Autodesk Fusion 360 part; units mm, degrees
(part 2 of 4)
revolve "Nest around the floor radius'" cut sketch "Sketch4 (3)" angle 90 about axis through (-24.07, -24.07, 3.45) along (0, 0, -1) bodies 4 in component "PRT-CORNER"
sketch "Sketch5 (2)" plane through (0, 0, 0) normal (0, 0, 1) x (1, 0, 0) in component "PRT-CORNER"
  line L0 (-23.8, -55) -> (-16.2, -55)
  line L1 (-16.2, -55) -> (-16.2, -40)
  line L2 (-16.2, -40) -> (-23.8, -40)
  line L3 (-23.8, -40) -> (-23.8, -55)
  dimension "d448" = 55
  dimension "d449" = 16.2
  dimension "d450" = 40
  dimension "d451" = 23.8
  constraint horizontal L0
  constraint vertical L1
  constraint horizontal L2
  constraint vertical L3
  measures "d448" vertical distance of origin L0.start
  measures "d449" horizontal distance of origin L0.end
  measures "d450" vertical distance of origin L1.end
  measures "d451" horizontal distance of origin L2.end
extrude "Extrude4''" add sketch "Sketch5 (2)" along normal blind 4.2 from surface at 15.8 bodies 4 in component "PRT-CORNER"
sketch "Sketch6 (2)" plane through (0, 0, 0) normal (0, 0, 1) x (1, 0, 0) in component "PRT-CORNER"
  line L0 (-55, -23.8) -> (-40, -23.8)
  line L1 (-40, -23.8) -> (-40, -16.2)
  line L2 (-40, -16.2) -> (-55, -16.2)
  line L3 (-55, -16.2) -> (-55, -23.8)
  dimension "d455" = 23.8
  dimension "d456" = 40
  dimension "d457" = 16.2
  dimension "d458" = 55
  constraint horizontal L0
  constraint vertical L1
  constraint horizontal L2
  constraint vertical L3
  measures "d455" vertical distance of origin L0.start
  measures "d456" horizontal distance of origin L0.end
  measures "d457" vertical distance of origin L1.end
  measures "d458" horizontal distance of origin L2.end
extrude "Extrude5'" add sketch "Sketch6 (2)" along normal blind 4.2 from surface at 15.8 bodies 4 in component "PRT-CORNER"
sketch "Sketch7 (2)" plane through (0, 0, 0) normal (0, 0, 1) x (1, 0, 0) in component "PRT-CORNER"
  line L0 (-23.8, -55) -> (-16.2, -55)
  line L1 (-16.2, -55) -> (-16.2, -40)
  line L2 (-16.2, -40) -> (-23.8, -40)
  line L3 (-23.8, -40) -> (-23.8, -55)
  dimension "d462" = 55
  dimension "d463" = 16.2
  dimension "d464" = 40
  dimension "d465" = 23.8
  constraint horizontal L0
  constraint vertical L1
  constraint horizontal L2
  constraint vertical L3
  measures "d462" vertical distance of origin L0.start
  measures "d463" horizontal distance of origin L0.end
  measures "d464" vertical distance of origin L1.end
  measures "d465" horizontal distance of origin L2.end
extrude "Extrude6'" add sketch "Sketch7 (2)" along normal blind 4.2 from surface at -20 bodies 4 in component "PRT-CORNER"
sketch "Sketch8 (2)" plane through (0, 0, 0) normal (0, 0, 1) x (1, 0, 0) in component "PRT-CORNER"
  line L0 (-55, -23.8) -> (-40, -23.8)
  line L1 (-40, -23.8) -> (-40, -16.2)
  line L2 (-40, -16.2) -> (-55, -16.2)
  line L3 (-55, -16.2) -> (-55, -23.8)
  dimension "d469" = 23.8
  dimension "d470" = 40
  dimension "d471" = 16.2
  dimension "d472" = 55
  constraint horizontal L0
  constraint vertical L1
  constraint horizontal L2
  constraint vertical L3
  measures "d469" vertical distance of origin L0.start
  measures "d470" horizontal distance of origin L0.end
  measures "d471" vertical distance of origin L1.end
  measures "d472" horizontal distance of origin L2.end
extrude "Extrude7'" add sketch "Sketch8 (2)" along normal blind 4.2 from surface at -20 bodies 4 in component "PRT-CORNER"
sketch "Sketch9 (2)" plane through (0, 0, 0) normal (0, 0, 1) x (1, 0, 0) in component "PRT-CORNER"
  line L0 (-40, -40) -> (0, -40)
  line L1 (0, -40) -> (0, 0)
  line L2 (0, 0) -> (-40, 0)
  line L3 (-40, 0) -> (-40, -40)
  dimension "d476" = 40
  dimension "d477" = 40
  constraint horizontal L0
  constraint vertical L1
  constraint vertical L1.end L0.end
  constraint horizontal L2
  constraint horizontal L1.end L2.start
  constraint vertical L3
  measures "d476" vertical distance of L1.end L0.start
  measures "d477" horizontal distance of L1.end L2.end
extrude "Extrude8'" add sketch "Sketch9 (2)" along normal blind 8 from surface at 20 bodies 4 in component "PRT-CORNER"
sketch "Sketch10 (2)" plane through (0, 0, 0) normal (0, 0, 1) x (1, 0, 0) in component "PRT-CORNER"
  line L0 (-40, -100) -> (0, -100)
  line L1 (0, -100) -> (0, -40)
  line L2 (0, -40) -> (-40, -40)
  line L3 (-40, -40) -> (-40, -100)
  dimension "d481" = 100
  dimension "d482" = 40
  dimension "d483" = 40
  constraint horizontal L0
  constraint vertical L1
  constraint vertical origin L0.end
  constraint horizontal L2
  constraint vertical L3
  measures "d481" vertical distance of origin L0.start
  measures "d482" vertical distance of origin L1.end
  measures "d483" horizontal distance of origin L2.end
extrude "Extrude9'" add sketch "Sketch10 (2)" along normal blind 8 from surface at 20 bodies 4 in component "PRT-CORNER"
sketch "Sketch11 (2)" plane through (0, 0, 0) normal (0, 0, 1) x (1, 0, 0) in component "PRT-CORNER"
  line L0 (-100, -40) -> (-40, -40)
  line L1 (-40, -40) -> (-40, 0)
  line L2 (-40, 0) -> (-100, 0)
  line L3 (-100, 0) -> (-100, -40)
  dimension "d487" = 40
  dimension "d488" = 40
  dimension "d489" = 100
  constraint horizontal L0
  constraint vertical L1
  constraint horizontal L2
  constraint horizontal origin L1.end
  constraint vertical L3
  measures "d487" vertical distance of origin L0.start
  measures "d488" horizontal distance of origin L0.end
  measures "d489" horizontal distance of origin L2.end
extrude "Extrude10'" add sketch "Sketch11 (2)" along normal blind 8 from surface at 20 bodies 4 in component "PRT-CORNER"
sketch "Sketch12 (2)" plane through (0, 0, 0) normal (0, 0, 1) x (1, 0, 0) in component "PRT-CORNER"
  circle A0 centre (-20, -70) radius 3.3
  dimension "d493" = 20
  dimension "d494" = 70
  dimension "d495" = 6.6
  measures "d493" horizontal distance of origin A0.centre
  measures "d494" vertical distance of origin A0.centre
  measures "d495" diameter of A0
extrude "Extrude11'" cut sketch "Sketch12 (2)" along normal blind 10 from surface at 19 bodies 4 in component "PRT-CORNER"
sketch "Sketch13 (2)" plane through (0, 0, 0) normal (0, 0, 1) x (1, 0, 0) in component "PRT-CORNER"
  circle A0 centre (-70, -20) radius 3.3
  dimension "d499" = 70
  dimension "d500" = 20
  dimension "d501" = 6.6
  measures "d499" horizontal distance of origin A0.centre
  measures "d500" vertical distance of origin A0.centre
  measures "d501" diameter of A0
extrude "Extrude12'" cut sketch "Sketch13 (2)" along normal blind 10 from surface at 19 bodies 4 in component "PRT-CORNER"
sketch "Sketch14 (2)" plane through (0, 0, 0) normal (0, 0, 1) x (1, 0, 0) in component "PRT-CORNER"
  line L0 (-40, -40) -> (0, -40)
  line L1 (0, -40) -> (0, 0)
  line L2 (0, 0) -> (-40, 0)
  line L3 (-40, 0) -> (-40, -40)
  dimension "d505" = 40
  dimension "d506" = 40
  constraint horizontal L0
  constraint vertical L1
  constraint vertical L1.end L0.end
  constraint horizontal L2
  constraint horizontal L1.end L2.start
  constraint vertical L3
  measures "d505" vertical distance of L1.end L0.start
  measures "d506" horizontal distance of L1.end L2.end
extrude "Extrude13'" add sketch "Sketch14 (2)" along normal blind 8 from surface at -28 bodies 4 in component "PRT-CORNER"
sketch "Sketch15 (2)" plane through (0, 0, 0) normal (0, 0, 1) x (1, 0, 0) in component "PRT-CORNER"
  line L0 (-40, -100) -> (0, -100)
  line L1 (0, -100) -> (0, -40)
  line L2 (0, -40) -> (-40, -40)
  line L3 (-40, -40) -> (-40, -100)
  dimension "d510" = 100
  dimension "d511" = 40
  dimension "d512" = 40
  constraint horizontal L0
  constraint vertical L1
  constraint vertical origin L0.end
  constraint horizontal L2
  constraint vertical L3
  measures "d510" vertical distance of origin L0.start
  measures "d511" vertical distance of origin L1.end
  measures "d512" horizontal distance of origin L2.end
extrude "Extrude14'" add sketch "Sketch15 (2)" along normal blind 8 from surface at -28 bodies 4 in component "PRT-CORNER"
sketch "Sketch16 (2)" plane through (0, 0, 0) normal (0, 0, 1) x (1, 0, 0) in component "PRT-CORNER"
  line L0 (-100, -40) -> (-40, -40)
  line L1 (-40, -40) -> (-40, 0)
  line L2 (-40, 0) -> (-100, 0)
  line L3 (-100, 0) -> (-100, -40)
  dimension "d516" = 40
  dimension "d517" = 40
  dimension "d518" = 100
  constraint horizontal L0
  constraint vertical L1
  constraint horizontal L2
  constraint horizontal origin L1.end
  constraint vertical L3
  measures "d516" vertical distance of origin L0.start
  measures "d517" horizontal distance of origin L0.end
  measures "d518" horizontal distance of origin L2.end
extrude "Extrude15'" add sketch "Sketch16 (2)" along normal blind 8 from surface at -28 bodies 4 in component "PRT-CORNER"
sketch "Sketch17 (2)" plane through (0, 0, 0) normal (0, 0, 1) x (1, 0, 0) in component "PRT-CORNER"
  circle A0 centre (-20, -70) radius 3.3
  dimension "d522" = 20
  dimension "d523" = 70
  dimension "d524" = 6.6
  measures "d522" horizontal distance of origin A0.centre
  measures "d523" vertical distance of origin A0.centre
  measures "d524" diameter of A0
extrude "Extrude16'" cut sketch "Sketch17 (2)" along normal blind 10 from surface at -29 bodies 4 in component "PRT-CORNER"
sketch "Sketch18 (2)" plane through (0, 0, 0) normal (0, 0, 1) x (1, 0, 0) in component "PRT-CORNER"
  circle A0 centre (-70, -20) radius 3.3
  measures "d528" distance of origin A0.centre
  measures "d529" distance of origin A0.centre
  measures "d530" diameter of A0
extrude "Extrude17'" cut sketch "Sketch18 (2)" along normal blind 10 from surface at -29 bodies 4 in component "PRT-CORNER"
ref_plane "WorkPlane3" through (0, 0, 12.125) normal (0.7071, 0.7071, 0) x (0, 0, 1) in component "PRT-CORNER"
ref_plane "WorkPlane4" through (-15.5847, -15.5847, 12.125) normal (0.7071, 0.7071, 0) x (0, 0, 1) in component "PRT-CORNER"
sketch "Sketch19 (2)" plane through (-15.5847, -15.5847, 0) normal (0.7071, 0.7071, 0) x (0, 0, 1) in component "PRT-CORNER"
  circle A0 centre (0, 0) radius 2.2
  dimension "d538" = 4.4
  constraint coincident A0.centre origin
  measures "d538" diameter of A0
extrude "Extrude18'" cut sketch "Sketch19 (2)" against normal blind 6.364 bodies 4 in component "PRT-CORNER"
sketch "Sketch1 (4)" plane through (0, 0, 0) normal (0, 0, 1) x (1, 0, 0) in component "Winding X (40 t AWG18)"
  line L0 (-679.53, -679.53) -> (679.53, -679.53)
  line L1 (679.53, -679.53) -> (679.53, 679.53)
  line L2 (679.53, 679.53) -> (-679.53, 679.53)
  line L3 (-679.53, 679.53) -> (-679.53, -679.53)
  dimension "d541" = 679.53
  dimension "d542" = 679.53
  dimension "d543" = 679.53
  dimension "d544" = 679.53
  constraint horizontal L0
  constraint vertical L1
  constraint horizontal L2
  constraint vertical L3
  measures "d541" vertical distance of origin L0.start
  measures "d542" horizontal distance of origin L0.end
  measures "d543" vertical distance of origin L1.end
  measures "d544" horizontal distance of origin L2.end
extrude "Extrude1''''" add sketch "Sketch1 (4)" along normal blind 9.9 from surface at -4.95 separate body makes body 5 in component "Winding X (40 t AWG18)"
sketch "Sketch2 (4)" plane through (0, 0, 0) normal (0, 0, 1) x (1, 0, 0) in component "Winding X (40 t AWG18)"
  line L0 (-678.43, -678.43) -> (678.43, -678.43)
  line L1 (678.43, -678.43) -> (678.43, 678.43)
  line L2 (678.43, 678.43) -> (-678.43, 678.43)
  line L3 (-678.43, 678.43) -> (-678.43, -678.43)
  dimension "d548" = 678.43
  dimension "d549" = 678.43
  dimension "d550" = 678.43
  dimension "d551" = 678.43
  constraint horizontal L0
  constraint vertical L1
  constraint horizontal L2
  constraint vertical L3
  measures "d548" vertical distance of origin L0.start
  measures "d549" horizontal distance of origin L0.end
  measures "d550" vertical distance of origin L1.end
  measures "d551" horizontal distance of origin L2.end
extrude "Extrude2'''" cut sketch "Sketch2 (4)" along normal blind 11.9 from surface at -5.95 bodies 5 in component "Winding X (40 t AWG18)"
fillet "Fillet1" radius 12 4 edges at (678.43, -678.43, 0) (-678.43, -678.43, 0) (-678.43, 678.43, 0) (678.43, 678.43, 0) on bodies 5 in component "Winding X (40 t AWG18)"
fillet "Fillet2" radius 13.1 4 edges at (-679.53, 679.53, 0) (679.53, 679.53, 0) (679.53, -679.53, 0) (-679.53, -679.53, 0) on bodies 5 in component "Winding X (40 t AWG18)"
sketch "Sketch3 (4)" plane through (0, 0, 0) normal (0, 0, 1) x (1, 0, 0) in component "Winding X (40 t AWG18)"
  line L0 (-680.4826, -680.4826) -> (680.4826, -680.4826)
  line L1 (680.4826, -680.4826) -> (680.4826, 680.4826)
  line L2 (680.4826, 680.4826) -> (-680.4826, 680.4826)
  line L3 (-680.4826, 680.4826) -> (-680.4826, -680.4826)
  dimension "d559" = 680.4826
  dimension "d560" = 680.4826
  dimension "d561" = 680.4826
  dimension "d562" = 680.4826
  constraint horizontal L0
  constraint vertical L1
  constraint horizontal L2
  constraint vertical L3
  measures "d559" vertical distance of origin L0.start
  measures "d560" horizontal distance of origin L0.end
  measures "d561" vertical distance of origin L1.end
  measures "d562" horizontal distance of origin L2.end
extrude "Extrude3'''" add sketch "Sketch3 (4)" along normal blind 11 from surface at -5.5 separate body makes body 6 in component "Winding X (40 t AWG18)"
sketch "Sketch4 (4)" plane through (0, 0, 0) normal (0, 0, 1) x (1, 0, 0) in component "Winding X (40 t AWG18)"
  line L0 (-679.3826, -679.3826) -> (679.3826, -679.3826)
  line L1 (679.3826, -679.3826) -> (679.3826, 679.3826)
  line L2 (679.3826, 679.3826) -> (-679.3826, 679.3826)
  line L3 (-679.3826, 679.3826) -> (-679.3826, -679.3826)
  dimension "d566" = 679.3826
  dimension "d567" = 679.3826
  dimension "d568" = 679.3826
  dimension "d569" = 679.3826
  constraint horizontal L0
  constraint vertical L1
  constraint horizontal L2
  constraint vertical L3
  measures "d566" vertical distance of origin L0.start
  measures "d567" horizontal distance of origin L0.end
  measures "d568" vertical distance of origin L1.end
  measures "d569" horizontal distance of origin L2.end
extrude "Extrude4'''" cut sketch "Sketch4 (4)" along normal blind 13 from surface at -6.5 bodies 6 in component "Winding X (40 t AWG18)"
fillet "Fillet3" radius 12.9526 4 edges at (679.3826, -679.3826, 0) (-679.3826, -679.3826, 0) (-679.3826, 679.3826, 0) (679.3826, 679.3826, 0) on bodies 6 in component "Winding X (40 t AWG18)"
fillet "Fillet4" radius 14.0526 4 edges at (-680.4826, 680.4826, 0) (680.4826, 680.4826, 0) (680.4826, -680.4826, 0) (-680.4826, -680.4826, 0) on bodies 6 in component "Winding X (40 t AWG18)"
sketch "Sketch5 (3)" plane through (0, 0, 0) normal (0, 0, 1) x (1, 0, 0) in component "Winding X (40 t AWG18)"
  line L0 (-681.4353, -681.4353) -> (681.4353, -681.4353)
  line L1 (681.4353, -681.4353) -> (681.4353, 681.4353)
  line L2 (681.4353, 681.4353) -> (-681.4353, 681.4353)
  line L3 (-681.4353, 681.4353) -> (-681.4353, -681.4353)
  dimension "d577" = 681.4353
  dimension "d578" = 681.4353
  dimension "d579" = 681.4353
  dimension "d580" = 681.4353
  constraint horizontal L0
  constraint vertical L1
  constraint horizontal L2
  constraint vertical L3
  measures "d577" vertical distance of origin L0.start
  measures "d578" horizontal distance of origin L0.end
  measures "d579" vertical distance of origin L1.end
  measures "d580" horizontal distance of origin L2.end
extrude "Extrude5''" add sketch "Sketch5 (3)" along normal blind 12.1 from surface at -6.05 separate body makes body 7 in component "Winding X (40 t AWG18)"
sketch "Sketch6 (3)" plane through (0, 0, 0) normal (0, 0, 1) x (1, 0, 0) in component "Winding X (40 t AWG18)"
  line L0 (-680.3353, -680.3353) -> (680.3353, -680.3353)
  line L1 (680.3353, -680.3353) -> (680.3353, 680.3353)
  line L2 (680.3353, 680.3353) -> (-680.3353, 680.3353)
  line L3 (-680.3353, 680.3353) -> (-680.3353, -680.3353)
  dimension "d584" = 680.3353
  dimension "d585" = 680.3353
  dimension "d586" = 680.3353
  dimension "d587" = 680.3353
  constraint horizontal L0
  constraint vertical L1
  constraint horizontal L2
  constraint vertical L3
  measures "d584" vertical distance of origin L0.start
  measures "d585" horizontal distance of origin L0.end
  measures "d586" vertical distance of origin L1.end
  measures "d587" horizontal distance of origin L2.end
extrude "Extrude6''" cut sketch "Sketch6 (3)" along normal blind 14.1 from surface at -7.05 bodies 7 in component "Winding X (40 t AWG18)"
fillet "Fillet5" radius 13.9053 4 edges at (680.3353, -680.3353, 0) (-680.3353, -680.3353, 0) (-680.3353, 680.3353, 0) (680.3353, 680.3353, 0) on bodies 7 in component "Winding X (40 t AWG18)"
fillet "Fillet6" radius 15.0053 4 edges at (-681.4353, 681.4353, 0) (681.4353, 681.4353, 0) (681.4353, -681.4353, 0) (-681.4353, -681.4353, 0) on bodies 7 in component "Winding X (40 t AWG18)"
sketch "Sketch7 (3)" plane through (0, 0, 0) normal (0, 0, 1) x (1, 0, 0) in component "Winding X (40 t AWG18)"
  line L0 (-682.3879, -682.3879) -> (682.3879, -682.3879)
  line L1 (682.3879, -682.3879) -> (682.3879, 682.3879)
  line L2 (682.3879, 682.3879) -> (-682.3879, 682.3879)
  line L3 (-682.3879, 682.3879) -> (-682.3879, -682.3879)
  dimension "d595" = 682.3879
  dimension "d596" = 682.3879
  dimension "d597" = 682.3879
  dimension "d598" = 682.3879
  constraint horizontal L0
  constraint vertical L1
  constraint horizontal L2
  constraint vertical L3
  measures "d595" vertical distance of origin L0.start
  measures "d596" horizontal distance of origin L0.end
  measures "d597" vertical distance of origin L1.end
  measures "d598" horizontal distance of origin L2.end
extrude "Extrude7''" add sketch "Sketch7 (3)" along normal blind 11 from surface at -5.5 separate body makes body 8 in component "Winding X (40 t AWG18)"
sketch "Sketch8 (3)" plane through (0, 0, 0) normal (0, 0, 1) x (1, 0, 0) in component "Winding X (40 t AWG18)"
  line L0 (-681.2879, -681.2879) -> (681.2879, -681.2879)
  line L1 (681.2879, -681.2879) -> (681.2879, 681.2879)
  line L2 (681.2879, 681.2879) -> (-681.2879, 681.2879)
  line L3 (-681.2879, 681.2879) -> (-681.2879, -681.2879)
  dimension "d602" = 681.2879
  dimension "d603" = 681.2879
  dimension "d604" = 681.2879
  dimension "d605" = 681.2879
  constraint horizontal L0
  constraint vertical L1
  constraint horizontal L2
  constraint vertical L3
  measures "d602" vertical distance of origin L0.start
  measures "d603" horizontal distance of origin L0.end
  measures "d604" vertical distance of origin L1.end
  measures "d605" horizontal distance of origin L2.end
extrude "Extrude8''" cut sketch "Sketch8 (3)" along normal blind 13 from surface at -6.5 bodies 8 in component "Winding X (40 t AWG18)"
fillet "Fillet7" radius 14.8579 4 edges at (681.2879, -681.2879, 0) (-681.2879, -681.2879, 0) (-681.2879, 681.2879, 0) (681.2879, 681.2879, 0) on bodies 8 in component "Winding X (40 t AWG18)"
fillet "Fillet8" radius 15.9579 4 edges at (-682.3879, 682.3879, 0) (682.3879, 682.3879, 0) (682.3879, -682.3879, 0) (-682.3879, -682.3879, 0) on bodies 8 in component "Winding X (40 t AWG18)"
combine "Combine1" operation add target body 5 tool bodies 6 7 8 in component "Winding X (40 t AWG18)"
sketch "Sketch1 (5)" plane through (0, 0, 0) normal (0, 1, 0) x (1, 0, 0) in component "PRT-CLIP"
  line L0 (2.5, 22.65) -> (2.5, -22.65)
  line L1 (2.5, -22.65) -> (-20, -22.65)
  line L2 (-20, -22.65) -> (-20, -20.15)
  line L3 (-20, -20.15) -> (-18.5, -18.8)
  line L4 (-18.5, -18.8) -> (-16, -18.8)
  line L5 (-16, -18.8) -> (-16, -20.15)
  line L6 (-16, -20.15) -> (0, -20.15)
  line L7 (0, -20.15) -> (0, -3.6)
  line L8 (0, -3.6) -> (-7.8121, -3.6)
  line L9 (-7.8121, -3.6) -> (-7.8121, 3.6)
  line L10 (-7.8121, 3.6) -> (0, 3.6)
  line L11 (0, 3.6) -> (0, 20.15)
  line L12 (0, 20.15) -> (-16, 20.15)
  line L13 (-16, 20.15) -> (-16, 18.8)
  line L14 (-16, 18.8) -> (-18.5, 18.8)
  line L15 (-18.5, 18.8) -> (-20, 20.15)
  line L16 (-20, 20.15) -> (-20, 22.65)
  line L17 (-20, 22.65) -> (2.5, 22.65)
  dimension "d613" = 2.5
  dimension "d614" = 22.65
  dimension "d615" = 20
  dimension "d616" = 18.8
  dimension "d617" = 16
  dimension "d618" = 20.15
  dimension "d619" = 3.6
  dimension "d620" = 7.8121
  dimension "d621" = 3.6
  dimension "d622" = 20.15
  dimension "d623" = 16
  dimension "d624" = 18.8
  dimension "d625" = 20
  dimension "d626" = 22.65
  dimension "d627" = 20.15
  dimension "d628" = 18.5
  dimension "d629" = 18.5
  dimension "d630" = 20.15
  constraint vertical L0
  constraint horizontal L1
  constraint vertical L2
  constraint horizontal L4
  constraint vertical L5
  constraint horizontal L6
  constraint vertical L7
  constraint vertical origin L6.end
  constraint horizontal L8
  constraint vertical L9
  constraint horizontal L10
  constraint vertical L11
  constraint vertical origin L10.end
  constraint horizontal L12
  constraint vertical L13
  constraint horizontal L14
  constraint vertical L16
  constraint horizontal L17
  measures "d613" horizontal distance of origin L0.start
  measures "d614" vertical distance of origin L0.end
  measures "d615" horizontal distance of origin L1.end
  measures "d616" vertical distance of origin L3.end
  measures "d617" horizontal distance of origin L4.end
  measures "d618" vertical distance of origin L5.end
  measures "d619" vertical distance of origin L7.end
  measures "d620" horizontal distance of origin L8.end
  measures "d621" vertical distance of origin L9.end
  measures "d622" vertical distance of origin L11.end
  measures "d623" horizontal distance of origin L12.end
  measures "d624" vertical distance of origin L13.end
  measures "d625" horizontal distance of origin L15.end
  measures "d626" vertical distance of origin L16.end
  measures "d627" vertical distance of origin L2.end
  measures "d628" horizontal distance of origin L3.end
  measures "d629" horizontal distance of origin L14.end
  measures "d630" vertical distance of origin L15.end
extrude "Extrude1'''''" add sketch "Sketch1 (5)" along normal blind 15 from surface at -7.5 separate body makes body 9 in component "PRT-CLIP"
sketch "Sketch1 (6)" plane through (0, 0, 0) normal (0, 0, 1) x (1, 0, 0) in component "PRT-TIE"
  line L0 (0, -10) -> (6, -10)
  line L1 (6, -10) -> (6, 10)
  line L2 (6, 10) -> (0, 10)
  line L3 (0, 10) -> (0, -10)
  dimension "d634" = 10
  dimension "d635" = 6
  dimension "d636" = 10
  constraint horizontal L0
  constraint vertical L1
  constraint horizontal L2
  constraint vertical L3
  constraint vertical origin L2.end
  measures "d634" vertical distance of origin L0.start
  measures "d635" horizontal distance of origin L0.end
  measures "d636" vertical distance of origin L1.end
extrude "Extrude1''''''" add sketch "Sketch1 (6)" along normal blind 14 from surface at -7 separate body makes body 10 in component "PRT-TIE"
sketch "Sketch2 (5)" plane through (0, 0, 0) normal (0, 0, 1) x (1, 0, 0) in component "PRT-TIE"
  line L0 (-4.5, -6) -> (0, -6)
  line L1 (0, -6) -> (0, 6)
  line L2 (0, 6) -> (-4.5, 6)
  line L3 (-4.5, 6) -> (-4.5, -6)
  dimension "d640" = 6
  dimension "d641" = 6
  dimension "d642" = 4.5
  constraint horizontal L0
  constraint vertical L1
  constraint vertical origin L0.end
  constraint horizontal L2
  constraint vertical L3
  measures "d640" vertical distance of origin L0.start
  measures "d641" vertical distance of origin L1.end
  measures "d642" horizontal distance of origin L2.end
extrude "Extrude2''''" add sketch "Sketch2 (5)" along normal blind 7.6 from surface at -3.8 bodies 10 in component "PRT-TIE"
sketch "Sketch3 (5)" plane through (0, 0, 0) normal (0, 0, 1) x (1, 0, 0) in component "PRT-TIE"
  line L0 (-6, -6) -> (-4.5, -6)
  line L1 (-4.5, -6) -> (-4.5, 6)
  line L2 (-4.5, 6) -> (-6, 6)
  line L3 (-6, 6) -> (-6, -6)
  dimension "d646" = 6
  dimension "d647" = 4.5
  dimension "d648" = 6
  dimension "d649" = 6
  constraint horizontal L0
  constraint vertical L1
  constraint horizontal L2
  constraint vertical L3
  measures "d646" vertical distance of origin L0.start
  measures "d647" horizontal distance of origin L0.end
  measures "d648" vertical distance of origin L1.end
  measures "d649" horizontal distance of origin L2.end
extrude "Extrude3''''" add sketch "Sketch3 (5)" along normal blind 10 from surface at -5 bodies 10 in component "PRT-TIE"
sketch "Sketch4 (5)" plane through (0, 0, 0) normal (0, 0, 1) x (1, 0, 0) in component "PRT-TIE"
  line L0 (-6.5, -7) -> (1, -7)
  line L1 (1, -7) -> (1, 7)
  line L2 (1, 7) -> (-6.5, 7)
  line L3 (-6.5, 7) -> (-6.5, -7)
  dimension "d653" = 7
  dimension "d654" = 1
  dimension "d655" = 7
  dimension "d656" = 6.5
  constraint horizontal L0
  constraint vertical L1
  constraint horizontal L2
  constraint vertical L3
  measures "d653" vertical distance of origin L0.start
  measures "d654" horizontal distance of origin L0.end
  measures "d655" vertical distance of origin L1.end
  measures "d656" horizontal distance of origin L2.end
extrude "Extrude4''''" cut sketch "Sketch4 (5)" along normal blind 1.6 from surface at -0.8 bodies 10 in component "PRT-TIE"
sketch "Sketch5 (4)" plane through (0, 0, 0) normal (0, 0, 1) x (1, 0, 0) in component "PRT-TIE"
  line L0 (2, -2.5) -> (4.5, -2.5)
  line L1 (4.5, -2.5) -> (4.5, 2.5)
  line L2 (4.5, 2.5) -> (2, 2.5)
  line L3 (2, 2.5) -> (2, -2.5)
  dimension "d660" = 2.5
  dimension "d661" = 4.5
  dimension "d662" = 2.5
  dimension "d663" = 2
  constraint horizontal L0
  constraint vertical L1
  constraint horizontal L2
  constraint vertical L3
  measures "d660" vertical distance of origin L0.start
  measures "d661" horizontal distance of origin L0.end
  measures "d662" vertical distance of origin L1.end
  measures "d663" horizontal distance of origin L2.end
extrude "Extrude5'''" cut sketch "Sketch5 (4)" along normal blind 16 from surface at -8 bodies 10 in component "PRT-TIE"
sketch "Sketch1 (7)" plane through (0, 0, 0) normal (0, 0, 1) x (1, 0, 0) in component "Anderson 1327G6"
  line L0 (0, 0) -> (7.9, 0)
  line L1 (7.9, 0) -> (7.9, 24.6)
  line L2 (7.9, 24.6) -> (0, 24.6)
  line L3 (0, 24.6) -> (0, 0)
  dimension "d667" = 7.9
  dimension "d668" = 24.6
  constraint horizontal L0
  constraint horizontal L0.start L3.end
  constraint vertical L1
  constraint horizontal L2
  constraint vertical L3
  constraint vertical L0.start L2.end
  measures "d667" horizontal distance of L0.start L0.end
  measures "d668" vertical distance of L0.start L1.end
extrude "Extrude1'''''''" add sketch "Sketch1 (7)" along normal blind 7.9 from surface at -3.95 separate body makes body 11 in component "Anderson 1327G6"
sketch "Sketch1 (8)" plane through (0, 0, 0) normal (0, 0, 1) x (1, 0, 0) in component "Anderson 1327"
  line L0 (0, 0) -> (7.9, 0)
  line L1 (7.9, 0) -> (7.9, 24.6)
  line L2 (7.9, 24.6) -> (0, 24.6)
  line L3 (0, 24.6) -> (0, 0)
  dimension "d672" = 7.9
  dimension "d673" = 24.6
  constraint horizontal L0
  constraint horizontal L0.start L3.end
  constraint vertical L1
  constraint horizontal L2
  constraint vertical L3
  constraint vertical L0.start L2.end
  measures "d672" horizontal distance of L0.start L0.end
  measures "d673" vertical distance of L0.start L1.end
extrude "Extrude1''''''''" add sketch "Sketch1 (8)" along normal blind 7.9 from surface at -3.95 separate body makes body 12 in component "Anderson 1327"
extrude "Extrude1'''''''''" add sketch "6575N25 section" along normal blind 1385 separate body makes body 13 in component "6575N25 x 1385"
sketch "Sketch1 (9)" plane through (0, 0, 0) normal (0, 0, 1) x (1, 0, 0) in component "Winding Y (40 t AWG18)"
  line L0 (-721.53, -721.53) -> (721.53, -721.53)
  line L1 (721.53, -721.53) -> (721.53, 721.53)
  line L2 (721.53, 721.53) -> (-721.53, 721.53)
  line L3 (-721.53, 721.53) -> (-721.53, -721.53)
  dimension "d679" = 721.53
  dimension "d680" = 721.53
  dimension "d681" = 721.53
  dimension "d682" = 721.53
  constraint horizontal L0
  constraint vertical L1
  constraint horizontal L2
  constraint vertical L3
  measures "d679" vertical distance of origin L0.start
  measures "d680" horizontal distance of origin L0.end
  measures "d681" vertical distance of origin L1.end
  measures "d682" horizontal distance of origin L2.end
extrude "Extrude1''''''''''" add sketch "Sketch1 (9)" along normal blind 9.9 from surface at -4.95 separate body makes body 14 in component "Winding Y (40 t AWG18)"
sketch "Sketch2 (6)" plane through (0, 0, 0) normal (0, 0, 1) x (1, 0, 0) in component "Winding Y (40 t AWG18)"
  line L0 (-720.43, -720.43) -> (720.43, -720.43)
  line L1 (720.43, -720.43) -> (720.43, 720.43)
  line L2 (720.43, 720.43) -> (-720.43, 720.43)
  line L3 (-720.43, 720.43) -> (-720.43, -720.43)
  dimension "d686" = 720.43
  dimension "d687" = 720.43
  dimension "d688" = 720.43
  dimension "d689" = 720.43
  constraint horizontal L0
  constraint vertical L1
  constraint horizontal L2
  constraint vertical L3
  measures "d686" vertical distance of origin L0.start
  measures "d687" horizontal distance of origin L0.end
  measures "d688" vertical distance of origin L1.end
  measures "d689" horizontal distance of origin L2.end
extrude "Extrude2'''''" cut sketch "Sketch2 (6)" along normal blind 11.9 from surface at -5.95 bodies 14 in component "Winding Y (40 t AWG18)"
fillet "Fillet1'" radius 12 4 edges at (720.43, -720.43, 0) (-720.43, -720.43, 0) (-720.43, 720.43, 0) (720.43, 720.43, 0) on bodies 14 in component "Winding Y (40 t AWG18)"
fillet "Fillet2'" radius 13.1 4 edges at (-721.53, 721.53, 0) (721.53, 721.53, 0) (721.53, -721.53, 0) (-721.53, -721.53, 0) on bodies 14 in component "Winding Y (40 t AWG18)"
sketch "Sketch3 (6)" plane through (0, 0, 0) normal (0, 0, 1) x (1, 0, 0) in component "Winding Y (40 t AWG18)"
  line L0 (-722.4826, -722.4826) -> (722.4826, -722.4826)
  line L1 (722.4826, -722.4826) -> (722.4826, 722.4826)
  line L2 (722.4826, 722.4826) -> (-722.4826, 722.4826)
  line L3 (-722.4826, 722.4826) -> (-722.4826, -722.4826)
  dimension "d697" = 722.4826
  dimension "d698" = 722.4826
  dimension "d699" = 722.4826
  dimension "d700" = 722.4826
  constraint horizontal L0
  constraint vertical L1
  constraint horizontal L2
  constraint vertical L3
  measures "d697" vertical distance of origin L0.start
  measures "d698" horizontal distance of origin L0.end
  measures "d699" vertical distance of origin L1.end
  measures "d700" horizontal distance of origin L2.end
extrude "Extrude3'''''" add sketch "Sketch3 (6)" along normal blind 11 from surface at -5.5 separate body makes body 15 in component "Winding Y (40 t AWG18)"
sketch "Sketch4 (6)" plane through (0, 0, 0) normal (0, 0, 1) x (1, 0, 0) in component "Winding Y (40 t AWG18)"
  line L0 (-721.3826, -721.3826) -> (721.3826, -721.3826)
  line L1 (721.3826, -721.3826) -> (721.3826, 721.3826)
  line L2 (721.3826, 721.3826) -> (-721.3826, 721.3826)
  line L3 (-721.3826, 721.3826) -> (-721.3826, -721.3826)
  dimension "d704" = 721.3826
  dimension "d705" = 721.3826
  dimension "d706" = 721.3826
  dimension "d707" = 721.3826
  constraint horizontal L0
  constraint vertical L1
  constraint horizontal L2
  constraint vertical L3
  measures "d704" vertical distance of origin L0.start
  measures "d705" horizontal distance of origin L0.end
  measures "d706" vertical distance of origin L1.end
  measures "d707" horizontal distance of origin L2.end
extrude "Extrude4'''''" cut sketch "Sketch4 (6)" along normal blind 13 from surface at -6.5 bodies 15 in component "Winding Y (40 t AWG18)"
fillet "Fillet3'" radius 12.9526 4 edges at (721.3826, -721.3826, 0) (-721.3826, -721.3826, 0) (-721.3826, 721.3826, 0) (721.3826, 721.3826, 0) on bodies 15 in component "Winding Y (40 t AWG18)"
fillet "Fillet4'" radius 14.0526 4 edges at (-722.4826, 722.4826, 0) (722.4826, 722.4826, 0) (722.4826, -722.4826, 0) (-722.4826, -722.4826, 0) on bodies 15 in component "Winding Y (40 t AWG18)"
sketch "Sketch5 (5)" plane through (0, 0, 0) normal (0, 0, 1) x (1, 0, 0) in component "Winding Y (40 t AWG18)"
  line L0 (-723.4353, -723.4353) -> (723.4353, -723.4353)
  line L1 (723.4353, -723.4353) -> (723.4353, 723.4353)
  line L2 (723.4353, 723.4353) -> (-723.4353, 723.4353)
  line L3 (-723.4353, 723.4353) -> (-723.4353, -723.4353)
  dimension "d715" = 723.4353
  dimension "d716" = 723.4353
  dimension "d717" = 723.4353
  dimension "d718" = 723.4353
  constraint horizontal L0
  constraint vertical L1
  constraint horizontal L2
  constraint vertical L3
  measures "d715" vertical distance of origin L0.start
  measures "d716" horizontal distance of origin L0.end
  measures "d717" vertical distance of origin L1.end
  measures "d718" horizontal distance of origin L2.end
extrude "Extrude5''''" add sketch "Sketch5 (5)" along normal blind 12.1 from surface at -6.05 separate body makes body 16 in component "Winding Y (40 t AWG18)"
sketch "Sketch6 (4)" plane through (0, 0, 0) normal (0, 0, 1) x (1, 0, 0) in component "Winding Y (40 t AWG18)"
  line L0 (-722.3353, -722.3353) -> (722.3353, -722.3353)
  line L1 (722.3353, -722.3353) -> (722.3353, 722.3353)
  line L2 (722.3353, 722.3353) -> (-722.3353, 722.3353)
  line L3 (-722.3353, 722.3353) -> (-722.3353, -722.3353)
  dimension "d722" = 722.3353
  dimension "d723" = 722.3353
  dimension "d724" = 722.3353
  dimension "d725" = 722.3353
  constraint horizontal L0
  constraint vertical L1
  constraint horizontal L2
  constraint vertical L3
  measures "d722" vertical distance of origin L0.start
  measures "d723" horizontal distance of origin L0.end
  measures "d724" vertical distance of origin L1.end
  measures "d725" horizontal distance of origin L2.end
extrude "Extrude6'''" cut sketch "Sketch6 (4)" along normal blind 14.1 from surface at -7.05 bodies 16 in component "Winding Y (40 t AWG18)"
fillet "Fillet5'" radius 13.9053 4 edges at (722.3353, -722.3353, 0) (-722.3353, -722.3353, 0) (-722.3353, 722.3353, 0) (722.3353, 722.3353, 0) on bodies 16 in component "Winding Y (40 t AWG18)"
fillet "Fillet6'" radius 15.0053 4 edges at (-723.4353, 723.4353, 0) (723.4353, 723.4353, 0) (723.4353, -723.4353, 0) (-723.4353, -723.4353, 0) on bodies 16 in component "Winding Y (40 t AWG18)"
sketch "Sketch7 (4)" plane through (0, 0, 0) normal (0, 0, 1) x (1, 0, 0) in component "Winding Y (40 t AWG18)"
  line L0 (-724.3879, -724.3879) -> (724.3879, -724.3879)
  line L1 (724.3879, -724.3879) -> (724.3879, 724.3879)
  line L2 (724.3879, 724.3879) -> (-724.3879, 724.3879)
  line L3 (-724.3879, 724.3879) -> (-724.3879, -724.3879)
  dimension "d733" = 724.3879
  dimension "d734" = 724.3879
  dimension "d735" = 724.3879
  dimension "d736" = 724.3879
  constraint horizontal L0
  constraint vertical L1
  constraint horizontal L2
  constraint vertical L3
  measures "d733" vertical distance of origin L0.start
  measures "d734" horizontal distance of origin L0.end
  measures "d735" vertical distance of origin L1.end
  measures "d736" horizontal distance of origin L2.end
extrude "Extrude7'''" add sketch "Sketch7 (4)" along normal blind 11 from surface at -5.5 separate body makes body 17 in component "Winding Y (40 t AWG18)"
sketch "Sketch8 (4)" plane through (0, 0, 0) normal (0, 0, 1) x (1, 0, 0) in component "Winding Y (40 t AWG18)"
  line L0 (-723.2879, -723.2879) -> (723.2879, -723.2879)
  line L1 (723.2879, -723.2879) -> (723.2879, 723.2879)
  line L2 (723.2879, 723.2879) -> (-723.2879, 723.2879)
  line L3 (-723.2879, 723.2879) -> (-723.2879, -723.2879)
  dimension "d740" = 723.2879
  dimension "d741" = 723.2879
  dimension "d742" = 723.2879
  dimension "d743" = 723.2879
  constraint horizontal L0
  constraint vertical L1
  constraint horizontal L2
  constraint vertical L3
  measures "d740" vertical distance of origin L0.start
  measures "d741" horizontal distance of origin L0.end
  measures "d742" vertical distance of origin L1.end
  measures "d743" horizontal distance of origin L2.end
extrude "Extrude8'''" cut sketch "Sketch8 (4)" along normal blind 13 from surface at -6.5 bodies 17 in component "Winding Y (40 t AWG18)"
fillet "Fillet7'" radius 14.8579 4 edges at (723.2879, -723.2879, 0) (-723.2879, -723.2879, 0) (-723.2879, 723.2879, 0) (723.2879, 723.2879, 0) on bodies 17 in component "Winding Y (40 t AWG18)"
fillet "Fillet8'" radius 15.9579 4 edges at (-724.3879, 724.3879, 0) (724.3879, 724.3879, 0) (724.3879, -724.3879, 0) (-724.3879, -724.3879, 0) on bodies 17 in component "Winding Y (40 t AWG18)"
combine "Combine1'" operation add target body 14 tool bodies 15 16 17 in component "Winding Y (40 t AWG18)"
extrude "Extrude1'''''''''''" add sketch "6575N25 section" along normal blind 1469 separate body makes body 18 in component "6575N25 x 1469"
sketch "Sketch1 (10)" plane through (0, 0, 0) normal (0, 0, 1) x (1, 0, 0) in component "Winding Z (40 t AWG18)"
  line L0 (-763.53, -763.53) -> (763.53, -763.53)
  line L1 (763.53, -763.53) -> (763.53, 763.53)
  line L2 (763.53, 763.53) -> (-763.53, 763.53)
  line L3 (-763.53, 763.53) -> (-763.53, -763.53)
  dimension "d753" = 763.53
  dimension "d754" = 763.53
  dimension "d755" = 763.53
  dimension "d756" = 763.53
  constraint horizontal L0
  constraint vertical L1
  constraint horizontal L2
  constraint vertical L3
  measures "d753" vertical distance of origin L0.start
  measures "d754" horizontal distance of origin L0.end
  measures "d755" vertical distance of origin L1.end
  measures "d756" horizontal distance of origin L2.end
extrude "Extrude1''''''''''''" add sketch "Sketch1 (10)" along normal blind 9.9 from surface at -4.95 separate body makes body 19 in component "Winding Z (40 t AWG18)"
sketch "Sketch2 (7)" plane through (0, 0, 0) normal (0, 0, 1) x (1, 0, 0) in component "Winding Z (40 t AWG18)"
  line L0 (-762.43, -762.43) -> (762.43, -762.43)
  line L1 (762.43, -762.43) -> (762.43, 762.43)
  line L2 (762.43, 762.43) -> (-762.43, 762.43)
  line L3 (-762.43, 762.43) -> (-762.43, -762.43)
  dimension "d760" = 762.43
  dimension "d761" = 762.43
  dimension "d762" = 762.43
  dimension "d763" = 762.43
  constraint horizontal L0
  constraint vertical L1
  constraint horizontal L2
  constraint vertical L3
  measures "d760" vertical distance of origin L0.start
  measures "d761" horizontal distance of origin L0.end
  measures "d762" vertical distance of origin L1.end
  measures "d763" horizontal distance of origin L2.end
extrude "Extrude2''''''" cut sketch "Sketch2 (7)" along normal blind 11.9 from surface at -5.95 bodies 19 in component "Winding Z (40 t AWG18)"
fillet "Fillet1''" radius 12 4 edges at (762.43, -762.43, 0) (-762.43, -762.43, 0) (-762.43, 762.43, 0) (762.43, 762.43, 0) on bodies 19 in component "Winding Z (40 t AWG18)"
fillet "Fillet2''" radius 13.1 4 edges at (-763.53, 763.53, 0) (763.53, 763.53, 0) (763.53, -763.53, 0) (-763.53, -763.53, 0) on bodies 19 in component "Winding Z (40 t AWG18)"
sketch "Sketch3 (7)" plane through (0, 0, 0) normal (0, 0, 1) x (1, 0, 0) in component "Winding Z (40 t AWG18)"
  line L0 (-764.4826, -764.4826) -> (764.4826, -764.4826)
  line L1 (764.4826, -764.4826) -> (764.4826, 764.4826)
  line L2 (764.4826, 764.4826) -> (-764.4826, 764.4826)
  line L3 (-764.4826, 764.4826) -> (-764.4826, -764.4826)
  dimension "d771" = 764.4826
  dimension "d772" = 764.4826
  dimension "d773" = 764.4826
  dimension "d774" = 764.4826
  constraint horizontal L0
  constraint vertical L1
  constraint horizontal L2
  constraint vertical L3
  measures "d771" vertical distance of origin L0.start
  measures "d772" horizontal distance of origin L0.end
  measures "d773" vertical distance of origin L1.end
  measures "d774" horizontal distance of origin L2.end
extrude "Extrude3''''''" add sketch "Sketch3 (7)" along normal blind 11 from surface at -5.5 separate body makes body 20 in component "Winding Z (40 t AWG18)"
sketch "Sketch4 (7)" plane through (0, 0, 0) normal (0, 0, 1) x (1, 0, 0) in component "Winding Z (40 t AWG18)"
  line L0 (-763.3826, -763.3826) -> (763.3826, -763.3826)
  line L1 (763.3826, -763.3826) -> (763.3826, 763.3826)
  line L2 (763.3826, 763.3826) -> (-763.3826, 763.3826)
  line L3 (-763.3826, 763.3826) -> (-763.3826, -763.3826)
  dimension "d778" = 763.3826
  dimension "d779" = 763.3826
  dimension "d780" = 763.3826
  dimension "d781" = 763.3826
  constraint horizontal L0
  constraint vertical L1
  constraint horizontal L2
  constraint vertical L3
  measures "d778" vertical distance of origin L0.start
  measures "d779" horizontal distance of origin L0.end
  measures "d780" vertical distance of origin L1.end
  measures "d781" horizontal distance of origin L2.end
extrude "Extrude4''''''" cut sketch "Sketch4 (7)" along normal blind 13 from surface at -6.5 bodies 20 in component "Winding Z (40 t AWG18)"
fillet "Fillet3''" radius 12.9526 4 edges at (763.3826, -763.3826, 0) (-763.3826, -763.3826, 0) (-763.3826, 763.3826, 0) (763.3826, 763.3826, 0) on bodies 20 in component "Winding Z (40 t AWG18)"
fillet "Fillet4''" radius 14.0526 4 edges at (-764.4826, 764.4826, 0) (764.4826, 764.4826, 0) (764.4826, -764.4826, 0) (-764.4826, -764.4826, 0) on bodies 20 in component "Winding Z (40 t AWG18)"
sketch "Sketch5 (6)" plane through (0, 0, 0) normal (0, 0, 1) x (1, 0, 0) in component "Winding Z (40 t AWG18)"
  line L0 (-765.4353, -765.4353) -> (765.4353, -765.4353)
  line L1 (765.4353, -765.4353) -> (765.4353, 765.4353)
  line L2 (765.4353, 765.4353) -> (-765.4353, 765.4353)
  line L3 (-765.4353, 765.4353) -> (-765.4353, -765.4353)
  dimension "d789" = 765.4353
  dimension "d790" = 765.4353
  dimension "d791" = 765.4353
  dimension "d792" = 765.4353
  constraint horizontal L0
  constraint vertical L1
  constraint horizontal L2
  constraint vertical L3
  measures "d789" vertical distance of origin L0.start
  measures "d790" horizontal distance of origin L0.end
  measures "d791" vertical distance of origin L1.end
  measures "d792" horizontal distance of origin L2.end
extrude "Extrude5'''''" add sketch "Sketch5 (6)" along normal blind 12.1 from surface at -6.05 separate body makes body 21 in component "Winding Z (40 t AWG18)"
sketch "Sketch6 (5)" plane through (0, 0, 0) normal (0, 0, 1) x (1, 0, 0) in component "Winding Z (40 t AWG18)"
  line L0 (-764.3353, -764.3353) -> (764.3353, -764.3353)
  line L1 (764.3353, -764.3353) -> (764.3353, 764.3353)
  line L2 (764.3353, 764.3353) -> (-764.3353, 764.3353)
  line L3 (-764.3353, 764.3353) -> (-764.3353, -764.3353)
  dimension "d796" = 764.3353
  dimension "d797" = 764.3353
  dimension "d798" = 764.3353
  dimension "d799" = 764.3353
  constraint horizontal L0
  constraint vertical L1
  constraint horizontal L2
  constraint vertical L3
  measures "d796" vertical distance of origin L0.start
  measures "d797" horizontal distance of origin L0.end
  measures "d798" vertical distance of origin L1.end
  measures "d799" horizontal distance of origin L2.end
extrude "Extrude6''''" cut sketch "Sketch6 (5)" along normal blind 14.1 from surface at -7.05 bodies 21 in component "Winding Z (40 t AWG18)"
fillet "Fillet5''" radius 13.9053 4 edges at (764.3353, -764.3353, 0) (-764.3353, -764.3353, 0) (-764.3353, 764.3353, 0) (764.3353, 764.3353, 0) on bodies 21 in component "Winding Z (40 t AWG18)"
fillet "Fillet6''" radius 15.0053 4 edges at (-765.4353, 765.4353, 0) (765.4353, 765.4353, 0) (765.4353, -765.4353, 0) (-765.4353, -765.4353, 0) on bodies 21 in component "Winding Z (40 t AWG18)"
sketch "Sketch7 (5)" plane through (0, 0, 0) normal (0, 0, 1) x (1, 0, 0) in component "Winding Z (40 t AWG18)"
  line L0 (-766.3879, -766.3879) -> (766.3879, -766.3879)
  line L1 (766.3879, -766.3879) -> (766.3879, 766.3879)
  line L2 (766.3879, 766.3879) -> (-766.3879, 766.3879)
  line L3 (-766.3879, 766.3879) -> (-766.3879, -766.3879)
  dimension "d807" = 766.3879
  dimension "d808" = 766.3879
  dimension "d809" = 766.3879
  dimension "d810" = 766.3879
  constraint horizontal L0
  constraint vertical L1
  constraint horizontal L2
  constraint vertical L3
  measures "d807" vertical distance of origin L0.start
  measures "d808" horizontal distance of origin L0.end
  measures "d809" vertical distance of origin L1.end
  measures "d810" horizontal distance of origin L2.end
extrude "Extrude7''''" add sketch "Sketch7 (5)" along normal blind 11 from surface at -5.5 separate body makes body 22 in component "Winding Z (40 t AWG18)"
sketch "Sketch8 (5)" plane through (0, 0, 0) normal (0, 0, 1) x (1, 0, 0) in component "Winding Z (40 t AWG18)"
  line L0 (-765.2879, -765.2879) -> (765.2879, -765.2879)
  line L1 (765.2879, -765.2879) -> (765.2879, 765.2879)
  line L2 (765.2879, 765.2879) -> (-765.2879, 765.2879)
  line L3 (-765.2879, 765.2879) -> (-765.2879, -765.2879)
  dimension "d814" = 765.2879
  dimension "d815" = 765.2879
  dimension "d816" = 765.2879
  dimension "d817" = 765.2879
  constraint horizontal L0
  constraint vertical L1
  constraint horizontal L2
  constraint vertical L3
  measures "d814" vertical distance of origin L0.start
  measures "d815" horizontal distance of origin L0.end
  measures "d816" vertical distance of origin L1.end
  measures "d817" horizontal distance of origin L2.end
extrude "Extrude8''''" cut sketch "Sketch8 (5)" along normal blind 13 from surface at -6.5 bodies 22 in component "Winding Z (40 t AWG18)"
fillet "Fillet7''" radius 14.8579 4 edges at (765.2879, -765.2879, 0) (-765.2879, -765.2879, 0) (-765.2879, 765.2879, 0) (765.2879, 765.2879, 0) on bodies 22 in component "Winding Z (40 t AWG18)"
fillet "Fillet8''" radius 15.9579 4 edges at (-766.3879, 766.3879, 0) (766.3879, 766.3879, 0) (766.3879, -766.3879, 0) (-766.3879, -766.3879, 0) on bodies 22 in component "Winding Z (40 t AWG18)"
combine "Combine1''" operation add target body 19 tool bodies 20 21 22 in component "Winding Z (40 t AWG18)"
sketch "Sketch1 (11)" plane through (0, 0, 0) normal (0, 0, 1) x (1, 0, 0) in component "PRT-SHIM"
  line L0 (0, -2) -> (40.6, -2)
  line L1 (40.6, -2) -> (40.6, 0)
  line L2 (40.6, 0) -> (0, 0)
  line L3 (0, 0) -> (0, -2)
  dimension "d825" = 2
  dimension "d826" = 40.6
  constraint horizontal L0
  constraint vertical L1
  constraint horizontal L2
  constraint horizontal L2.end L1.end
  constraint vertical L3
  constraint vertical L2.end L3.start
  measures "d825" vertical distance of L2.end L0.start
  measures "d826" horizontal distance of L2.end L0.end
extrude "Extrude1'''''''''''''" add sketch "Sketch1 (11)" along normal blind 36 from surface at -18 separate body makes body 23 in component "PRT-SHIM"
sketch "Sketch2 (8)" plane through (0, 0, 0) normal (0, 1, 0) x (1, 0, 0) in component "PRT-SHIM"
  circle A0 centre (20, 0) radius 4.5
  dimension "d830" = 20
  dimension "d831" = 9
  constraint horizontal origin A0.centre
  measures "d830" horizontal distance of origin A0.centre
  measures "d831" diameter of A0
extrude "Extrude2'''''''" cut sketch "Sketch2 (8)" along normal blind 4 from surface at -3 bodies 23 in component "PRT-SHIM"
extrude "Extrude1''''''''''''''" add sketch "6575N25 section" along normal blind 100 separate body makes body 24 in component "6575N25 x 100"
sketch "Sketch1 (12)" plane through (0, 0, 0) normal (0, 0, 1) x (1, 0, 0) in component "5537T983"
  circle A0 centre (0, 0) radius 4
  dimension "d837" = 8
  constraint vertical A0.centre origin
  constraint horizontal A0.centre origin
  measures "d837" diameter of A0
extrude "Extrude1'''''''''''''''" add sketch "Sketch1 (12)" along normal blind 32 from surface at -32 separate body makes body 25 in component "5537T983"
sketch "Sketch2 (9)" plane through (0, 0, 0) normal (0, 0, 1) x (1, 0, 0) in component "5537T983"
  circle A0 centre (0, 0) radius 26
  dimension "d841" = 52
  constraint vertical A0.centre origin
  constraint horizontal A0.centre origin
  measures "d841" diameter of A0
extrude "Extrude2''''''''" add sketch "Sketch2 (9)" along normal blind 12 from surface at -44 bodies 25 in component "5537T983"
extrude "Extrude1''''''''''''''''" add sketch "6575N25 section" along normal blind 682.5 separate body makes body 26 in component "6575N25 x 682.5"
sketch "Sketch1 (13)" plane through (0, 0, 0) normal (0, 0, 1) x (1, 0, 0) in component "PRT-HANGER"
  line L0 (-80, -15) -> (80, -15)
  line L1 (80, -15) -> (80, 15)
  line L2 (80, 15) -> (-80, 15)
  line L3 (-80, 15) -> (-80, -15)
  dimension "d847" = 15
  dimension "d848" = 80
  dimension "d849" = 15
  dimension "d850" = 80
  constraint horizontal L0
  constraint vertical L1
  constraint horizontal L2
  constraint vertical L3
  measures "d847" vertical distance of origin L0.start
  measures "d848" horizontal distance of origin L0.end
  measures "d849" vertical distance of origin L1.end
  measures "d850" horizontal distance of origin L2.end
extrude "Extrude1'''''''''''''''''" add sketch "Sketch1 (13)" along normal blind 12 from surface at -12 separate body makes body 27 in component "PRT-HANGER"
sketch "Sketch2 (10)" plane through (0, 0, 0) normal (0, 0, 1) x (1, 0, 0) in component "PRT-HANGER"
  line L0 (-30, -3.8) -> (30, -3.8)
  line L1 (30, -3.8) -> (30, 3.8)
  line L2 (30, 3.8) -> (-30, 3.8)
  line L3 (-30, 3.8) -> (-30, -3.8)
  dimension "d854" = 3.8
  dimension "d855" = 30
  dimension "d856" = 3.8
  dimension "d857" = 30
  constraint horizontal L0
  constraint vertical L1
  constraint horizontal L2
  constraint vertical L3
  measures "d854" vertical distance of origin L0.start
  measures "d855" horizontal distance of origin L0.end
  measures "d856" vertical distance of origin L1.end
  measures "d857" horizontal distance of origin L2.end
extrude "Extrude2'''''''''" add sketch "Sketch2 (10)" along normal blind 3.8 bodies 27 in component "PRT-HANGER"
sketch "Sketch3 (8)" plane through (0, 0, 0) normal (0, 0, 1) x (1, 0, 0) in component "PRT-HANGER"
  circle A0 centre (0, 0) radius 3.3
  dimension "d860" = 6.6
  constraint vertical A0.centre origin
  constraint horizontal A0.centre origin
  measures "d860" diameter of A0
extrude "Extrude3'''''''" cut sketch "Sketch3 (8)" along normal blind 18 from surface at -13 bodies 27 in component "PRT-HANGER"